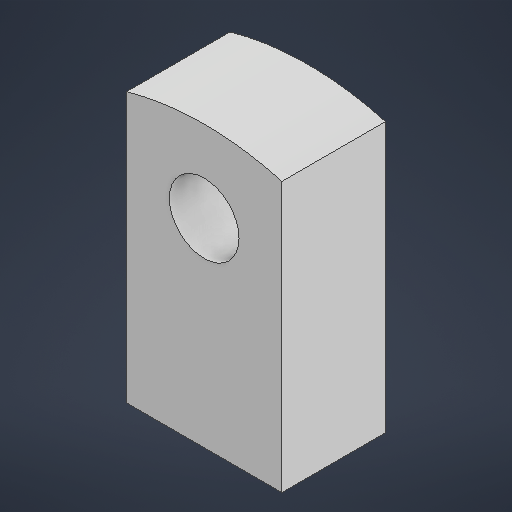
# Autodesk Inventor part: Linear Actuator Tip
Saved by Autodesk Inventor 2026.2 (Build 302298000, 298)
## iProperties
Created: 2026-11-10
Part Number: Linear Actuator Tip
Material: Generic
Document SubType Name: Modeling
Designer: Carro
Density: 1 g/cm^3
Appearance: Default
Author: Carro
Autodesk Inventor part; units mm, degrees
ref_plane "YZ Plane" through (0, 0, 0) normal (1, 0, 0) x (0, 1, 0)
ref_plane "XZ Plane" through (0, 0, 0) normal (0, 1, 0) x (-1, 0, 0)
ref_plane "XY Plane" through (0, 0, 0) normal (0, 0, 1) x (1, 0, 0)
sketch "Sketch1" plane through (0, 0, 0) normal (0, 0, 1) x (1, 0, 0)
  circle A0 centre (0, 0) radius 2.05
  line L0 (0, 0) -> (0, 4.8) construction
  line L1 (-4.572, -11.6949) -> (4.572, -11.6949)
  line L2 (0, 0) -> (0, -11.6949) construction
  line L3 (-4.572, -11.6949) -> (-4.572, 4.165)
  arc A1 (4.572, 4.165) -> (-4.572, 4.165) centre (0, -11.9767) ccw
  line L4 (4.572, 4.165) -> (4.572, -11.6949)
  point P0 (0, 2.05)
  point P1 (0, 4.8)
  dimension "d0" = 4.1
  dimension "d1" = 4.8
  dimension "d2" = 9.144
  dimension "d3" = 0.635
  constraints: 10 end point, 4 point on circle, 4 vertical, 1 centre point, 1 coincident, 1 horizontal, 1 midpoint, 1 parallel, 1 point on line, 1 vertical alignment, 2 other
  measures "d1" distance of L0.start L0.end
  measures "d2" distance of L1.start L1.end
  measures "d3" vertical distance of L3.end point (0, 4.8)
extrude "Extrusion1" add sketch "Sketch1" along normal mid plane 6.096
body "Solid1"
